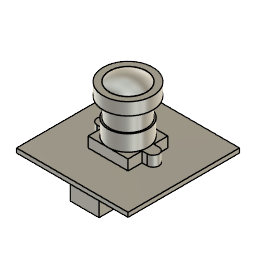
MechanoTest (Autodesk Fusion 360 archive; units mm, degrees)
design "SM205 Camera"
Autodesk Fusion 360 part; units mm, degrees
sketch "Sketch1" plane through (0, 0, 0) normal (0, 0, 1) x (1, 0, 0)
  line L0 (18.9, -18.9) -> (-18.9, -18.9)
  line L1 (-18.9, -18.9) -> (-18.9, 18.9)
  line L2 (-18.9, 18.9) -> (18.9, 18.9)
  line L3 (18.9, 18.9) -> (18.9, -18.9)
  line L4 (18.9, -18.9) -> (-18.9, 18.9) construction
  line L5 (-18.9, -18.9) -> (18.9, 18.9) construction
  dimension "d1" = 37.8
  dimension "d2" = 37.8
  constraint horizontal L0
  constraint perpendicular L0 L1
  constraint parallel L0 L2
  constraint parallel L1 L3
  constraint coincident L4 origin
  constraint coincident L5 origin
  measures "d1" distance of L1.end L2.end
  measures "d2" distance of L0.end L1.end
extrude "Extrude1" add sketch "Sketch1" along normal blind 1.5 makes body 1
sketch "Sketch2" plane through (0, 0, 0) normal (0, 0, -1) x (1, 0, 0)
  line L0 (-18.9, -18.9) -> (18.9, -18.9)
  line L1 (18.9, -18.9) -> (18.9, 18.9)
  line L2 (18.9, 18.9) -> (-18.9, 18.9)
  line L3 (-18.9, 18.9) -> (-18.9, -18.9)
  line L4 (5.9, 11.1) -> (-3.9, 11.1)
  line L5 (-3.9, 11.1) -> (-3.9, 15.7)
  line L6 (-3.9, 15.7) -> (5.9, 15.7)
  line L7 (5.9, 15.7) -> (5.9, 11.1)
  dimension "d5" = 9.8
  dimension "d6" = 4.6
  dimension "d7" = 15
  dimension "d8" = 7.8
  constraint horizontal L4
  constraint vertical L5
  constraint horizontal L6
  constraint vertical L7
  measures "d5" distance of L4.start L4.end
  measures "d6" distance of L4.start L6.end
  measures "d7" distance of L3 L5
  measures "d8" distance of L2 L4
extrude "Extrude2" add sketch "Sketch2" along normal blind 8.2 contours L4 L5 L6 L7 bodies 1
sketch "Sketch3" plane through (0, 0, 1.5) normal (0, 0, 1) x (-1, 0, 0)
  line L0 (-18.9, -18.9) -> (18.9, -18.9)
  line L1 (18.9, -18.9) -> (18.9, 18.9)
  line L2 (18.9, 18.9) -> (-18.9, 18.9)
  line L3 (-18.9, 18.9) -> (-18.9, -18.9)
  line L4 (-6.75, 6.75) -> (6.75, 6.75)
  line L5 (6.75, 6.75) -> (6.75, -6.75)
  line L6 (6.75, -6.75) -> (-6.75, -6.75)
  line L7 (-6.75, -6.75) -> (-6.75, 6.75)
  line L8 (-6.75, 6.75) -> (6.75, -6.75) construction
  line L9 (6.75, 6.75) -> (-6.75, -6.75) construction
  line L10 (0, 0) -> (0, -2)
  line L11 (-8.5, -2) -> (-6.75, -2)
  line L12 (-8.5, 2) -> (-6.75, 2)
  arc A0 (-8.5, 2) -> (-8.5, -2) centre (-8.5, 0) ccw
  line L13 (8.5, -2) -> (6.75, -2)
  arc A1 (8.5, -2) -> (8.5, 2) centre (8.5, 0) ccw
  line L14 (8.5, 2) -> (6.75, 2)
  circle A2 centre (0, 0) radius 6.75
  circle A3 centre (0, 0) radius 6.25
  dimension "d11" = 13.5
  dimension "d12" = 13.5
  dimension "d13" = 4
  dimension "d14" = 10.4
  dimension "d15" = 13.5
  dimension "d16" = 12.5
  constraint horizontal L4
  constraint perpendicular L4 L5
  constraint parallel L4 L6
  constraint parallel L5 L7
  constraint coincident L8 L10.start
  constraint coincident L9 L10.start
  constraint coincident L10.start A2.centre
  constraint parallel L3 L10
  constraint coincident L7 L11.end
  constraint perpendicular L7 L11
  constraint coincident L7 L12.end
  constraint perpendicular L7 L12
  constraint tangent L11 A0
  constraint tangent L12 A0
  constraint horizontal L10.start A0.centre
  constraint symmetric L10 L11.start L13.start
  constraint symmetric L10 L11.end L13.end
  constraint symmetric L10 L12.start A1.end
  constraint symmetric L10 L12.end L14.end
  constraint symmetric L10 A0 A1
  measures "d11" distance of L5.end L6.end
  measures "d12" distance of L4.end L5.end
  measures "d13" diameter of A0
  measures "d14" distance of L3 A0.centre
  measures "d15" diameter of A2
  measures "d16" diameter of A3
extrude "Extrude3" add sketch "Sketch3" along normal blind 3.5 separate body contours L4 L7 A2 | L4 L5 A2 | L7 L11 L12 A0 | L5 L13 A1 L14 | L5 L6 A2 | L6 L7 A2 makes body 2
extrude "Extrude4" add sketch "Sketch3" along normal blind 8.9 contours A2 bodies 1 2
extrude "Extrude5" add 1 faces at (3.0203, -1.0762, 1.5) along direction (0, 0, 1) blind 15.3 on bodies 1 bodies 1
sketch "Sketch4" plane through (0, 0, 16.8) normal (0, 0, 1) x (-1, 0, 0)
  circle A0 centre (0, 0) radius 6.25
  circle A1 centre (0, 0) radius 8.4
  dimension "d23" = 16.8
  constraint coincident A0.centre A1.centre
  measures "d23" diameter of A1
extrude "Extrude6" add sketch "Sketch4" along normal blind 4.2 bodies 1
ref_plane "WorkPlane1" through (0, 0, 20.8) normal (0, 0, 1) x (1, 0, 0)
sketch "Sketch5" plane through (0, 0, 20.8) normal (0, 0, 1) x (1, 0, 0)
sketch "Sketch6" plane through (0, 0, 0) normal (1, 0, 0) x (0, 1, 0)
  line L0 (8.4, 16.8) -> (-8.4, 16.8)
  line L1 (6.25, 16.8) -> (-6.25, 16.8)
  line L2 (-6.25, 10.4) -> (6.25, 10.4)
  line L3 (6.25, 16.8) -> (6.25, 20.95)
  arc A0 (6.25, 20.95) -> (0, 22.8981) centre (0, 11.8981) ccw
  line L4 (0, 22.8981) -> (0, 16.8)
  line L5 (0, 0) -> (0, 0.2255)
  line L6 (0, 0.2255) -> (0, 3.0895)
  dimension "d28" = 4.15
  dimension "d29" = 11
  constraint coincident L1.start L3.start
  constraint perpendicular L1 L3
  constraint midpoint L1 L4.end
  constraint vertical A0.centre A0.end
  constraint coincident L5.start origin
  constraint vertical L5
  constraint parallel L5 L6
  constraint vertical A0.end L6.end
  measures "d28" distance of L1.start L3.end
  measures "d29" radius of A0
revolve "Revolve1" add sketch "Sketch6" angle 360 about axis through (0, 0, 16.8) along (0, 0, -1) bodies 1
equation "d9 = 9.7 mm - 1.5 mm"
equation "d14 = 8.4 mm + 2 mm"
equation "d17 = 5 mm - 1.5 mm"
equation "d19 = 10.4 mm - 1.5 mm"
equation "d21 = 21.1 mm - 4.3 mm - 1.5 mm"
